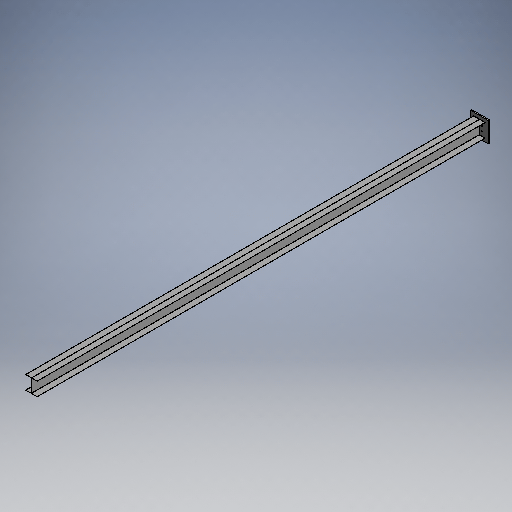
# Autodesk Inventor part: Column_HBeam_W12
Saved by Autodesk Inventor 2026.2 (Build 302298000, 298)
## iProperties
Part Number: Column_HBeam_W12
Material: Generic
Document SubType Name: Modeling
Designer: Jacob
Appearance: Default
Author: Jacob
Autodesk Inventor part; units mm, degrees
ref_plane "YZ Plane" through (0, 0, 0) normal (1, 0, 0) x (0, 1, 0)
ref_plane "XZ Plane" through (0, 0, 0) normal (0, 1, 0) x (-1, 0, 0)
ref_plane "XY Plane" through (0, 0, 0) normal (0, 0, 1) x (1, 0, 0)
sketch "Sketch1" plane through (0, 0, 0) normal (0, 0, 1) x (1, 0, 0)
  line L0 (-200, -225) -> (200, -225)
  line L1 (200, -225) -> (200, 225)
  line L2 (200, 225) -> (-200, 225)
  line L3 (-200, 225) -> (-200, -225)
  circle A0 centre (-51, -51) radius 15
  circle A1 centre (-51, 51) radius 15
  circle A2 centre (51, -51) radius 15
  circle A3 centre (51, 51) radius 15
  constraints: 8 end point, 4 centre point, 2 parallel, 1 horizontal, 1 perpendicular
extrude "Extrusion1" add sketch "Sketch1" along normal blind 25
sketch "Sketch2" plane through (0, 0, 0) normal (0, 0, 1) x (1, 0, 0)
  line L0 (-127.45, 148.15) -> (127.45, 148.15)
  line L1 (127.45, 148.15) -> (127.45, 152.95)
  line L2 (127.45, 152.95) -> (-127.45, 152.95)
  line L3 (-127.45, 152.95) -> (-127.45, 148.15)
  line L4 (-127.45, -152.95) -> (127.45, -152.95)
  line L5 (127.45, -152.95) -> (127.45, -148.15)
  line L6 (127.45, -148.15) -> (-127.45, -148.15)
  line L7 (-127.45, -148.15) -> (-127.45, -152.95)
  line L8 (-3.2, -148.15) -> (3.2, -148.15)
  line L9 (3.2, -148.15) -> (3.2, 148.15)
  line L10 (3.2, 148.15) -> (-3.2, 148.15)
  line L11 (-3.2, 148.15) -> (-3.2, -148.15)
  constraints: 24 end point, 6 parallel, 3 horizontal, 3 perpendicular
extrude "Extrusion2" add sketch "Sketch2" along normal blind 10000
body "Solid1"
